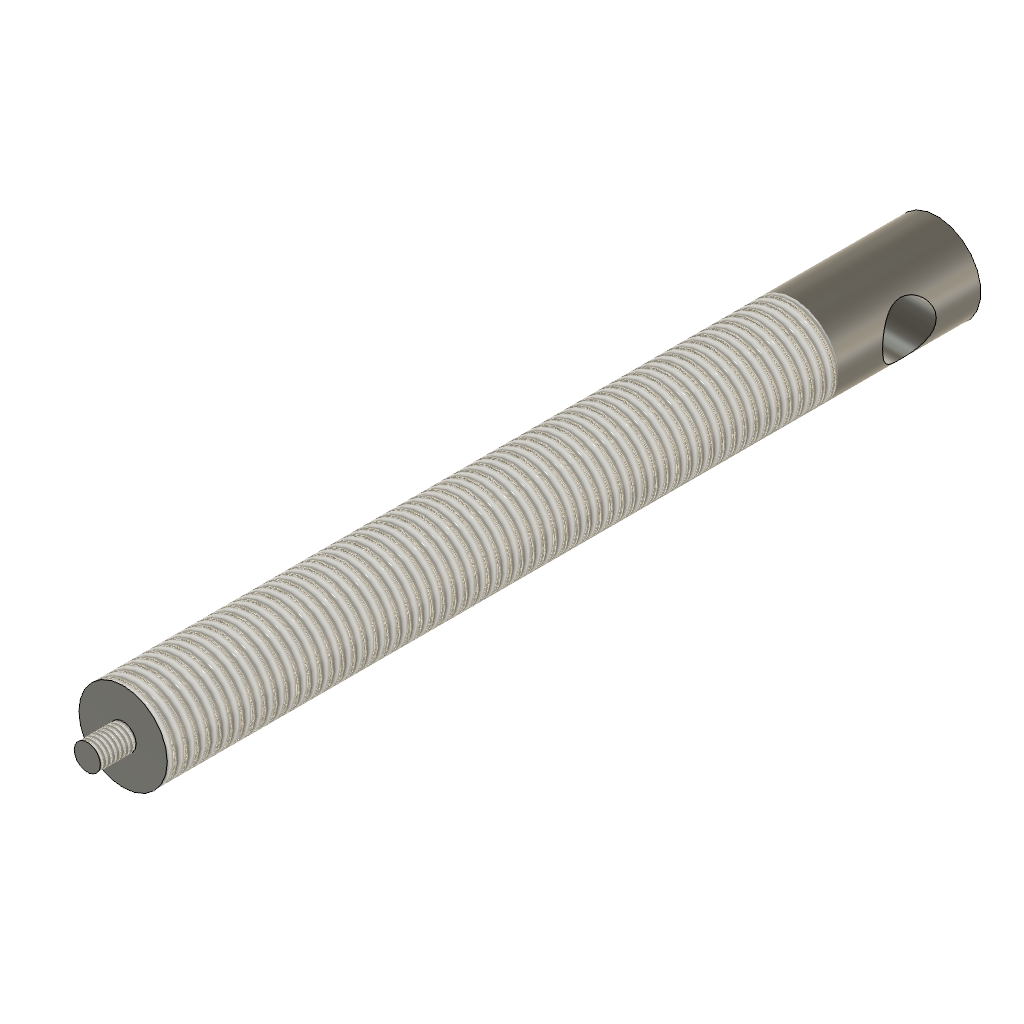
screw (Autodesk Fusion 360 design; units mm, degrees)
part number: 2026-10-15-14-35-36-033
Autodesk Fusion 360 part; units mm, degrees
sketch "Sketch1" plane through (0, 0, 0) normal (0, 1, 0) x (1, 0, 0)
  circle A0 centre (0, 0) radius 10
  dimension "d1" = 20
  constraint coincident A0.centre origin
  measures "d1" diameter of A0
extrude "Extrude1" add sketch "Sketch1" along normal blind 190
thread "Thread1" "ISO Metric profile 20.0 M20x2.5 M20x2.5 6g" major diameter 19.7905 minor diameter 16.938 pitch 2.5 angle 60 resizes the face on face at (9.9876, 126.6667, 0.4985) from (0, 0, 0) to (0, 158, 0)
sketch "Sketch2" plane through (0, 0, 0) normal (1, 0, 0) x (0, 1, 0)
  line L0 (0, 10) -> (8, 10)
  line L1 (8, 10) -> (8, -10)
  line L2 (8, -10) -> (0, -10)
  line L3 (0, -10) -> (0, 10)
  dimension "d6" = 8
  dimension "d7" = 20
  constraint horizontal L0
  constraint vertical L1
  constraint horizontal L2
  constraint vertical L3
  measures "d6" distance of L0.start L0.end
  measures "d7" distance of L0.start L2.end
extrude "Extrude2" cut sketch "Sketch2" along normal mid plane 50
sketch "Sketch3" plane through (0, 8, 0) normal (0, -1, 0) x (1, 0, 0)
  circle A0 centre (0, 0) radius 9.8953
  circle A1 centre (0, 0) radius 3
  dimension "d10" = 6
  constraint coincident A0.centre A1.centre
  measures "d10" diameter of A1
extrude "Extrude3" add sketch "Sketch3" along normal blind 8 contours A1
thread "Thread2" "ISO Metric profile 6.0 M6x1 M6x1 6g" major diameter 5.884 minor diameter 4.7435 pitch 1 angle 60 resizes the face on face at (2.9851, 2.6667, -0.2987)
sketch "Sketch4" plane through (0, 0, 0) normal (1, 0, 0) x (0, 1, 0)
  line L0 (190, 10) -> (174, 10)
  line L1 (174, 10) -> (174, 0)
  line L2 (174, 0) -> (190, 0)
  line L3 (190, 0) -> (190, 10)
  circle A0 centre (174, 0) radius 6
  dimension "d15" = 16
  dimension "d16" = 10
  dimension "d17" = 12
  constraint horizontal L0
  constraint vertical L1
  constraint horizontal L2
  constraint vertical L3
  constraint coincident L1.end L2.start
  measures "d15" distance of L0.start L0.end
  measures "d16" distance of L0.start L2.end
  measures "d17" diameter of A0
extrude "Extrude4" cut sketch "Sketch4" along normal mid plane 50 contours L1 L2 A0 | L1 L2 A0
